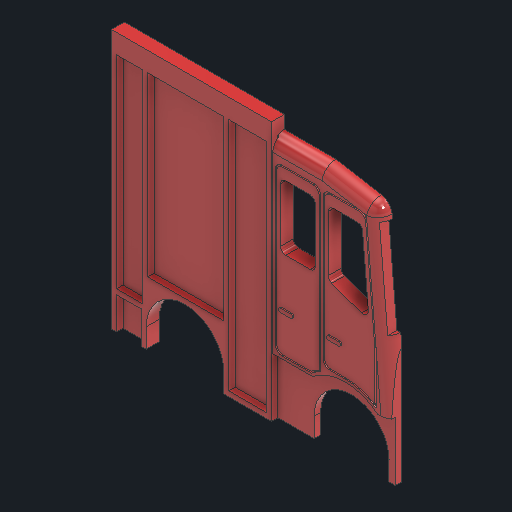
# Autodesk Inventor part: 7_1_1_cote_droit_base
Saved by Autodesk Inventor 2026 (Build 300175000, 175)
## iProperties
Created: 2025-06-21
Part Number: 7_1_1_cote_droit_base
Material: Generic
Document SubType Name: Modeling
Designer: remg9
Density: 1 g/cm^3
Appearance: Default
Author: remg9
Autodesk Inventor part; units mm, degrees
ref_plane "YZ Plane" through (0, 0, 0) normal (1, 0, 0) x (0, 1, 0)
ref_plane "XZ Plane" through (0, 0, 0) normal (0, 1, 0) x (-1, 0, 0)
ref_plane "XY Plane" through (0, 0, 0) normal (0, 0, 1) x (1, 0, 0)
sketch "Sketch1" plane through (0, 0, 0) normal (0, 0, 1) x (1, 0, 0)
  line L0 (0, 0) -> (215, 0) construction
  line L1 (215, 0) -> (215, 201) construction
  line L2 (215, 201) -> (0, 201) construction
  line L3 (0, 201) -> (0, 0)
  circle A0 centre (181, 15) radius 29 construction
  circle A1 centre (57, 15) radius 30 construction
  line L4 (0, 15) -> (215, 15) construction
  line L5 (124, 201) -> (124, 0) construction
  line L6 (0, 201) -> (124, 201)
  line L7 (124, 191) -> (215, 191) construction
  line L8 (164, 15) -> (164, 191) construction
  line L9 (124, 201) -> (124, 191)
  line L10 (124, 191) -> (164, 191)
  line L11 (215, 90) -> (0, 90) construction
  line L12 (215, 0) -> (215, 90)
  line L13 (215, 90) -> (191.4139, 359.5906) construction
  line L14 (164, 191) -> (320.5108, 163.4029) construction
  line L15 (210, 15) -> (210, 0) construction
  line L16 (152, 15) -> (152, 0) construction
  line L17 (87, 15) -> (87, 0) construction
  line L18 (27, 15) -> (27, 0) construction
  line L19 (0, 0) -> (27, 0)
  line L20 (27, 0) -> (27, 15)
  line L21 (87, 15) -> (87, 0)
  line L22 (152, 0) -> (152, 15)
  line L23 (87, 0) -> (152, 0)
  line L24 (210, 15) -> (210, 0)
  line L25 (210, 0) -> (215, 0)
  line L26 (164, 191) -> (199.2676, 184.7814)
  line L27 (215, 90) -> (207.493, 175.8049)
  arc A2 (87, 15) -> (27, 15) centre (57, 15) ccw
  arc A3 (210, 15) -> (152, 15) centre (181, 15) ccw
  arc A4 (207.493, 175.8049) -> (199.2676, 184.7814) centre (197.5311, 174.9333) ccw
  point P0 (84, 0)
  point P1 (24, 0)
  point P2 (206.8243, 183.4489)
  dimension "d0" = 201
  dimension "d1" = 215
  dimension "d2" = 58
  dimension "d3" = 60
  dimension "d4" = 34
  dimension "d5" = 57
  dimension "d6" = 15
  dimension "d7" = 15
  dimension "d8" = 91
  dimension "d9" = 10
  dimension "d10" = 40
  dimension "d11" = 90
  dimension "d12" = 10
  dimension "d13" = 5
  dimension "d14" = 10
  dimension "d44" = 5
  dimension "d99" = 124
  constraints: 54 end point, 17 point on line, 10 point on circle, 9 tangent, 6 collinear, 5 centre point, 5 vertical, 4 horizontal, 4 perpendicular, 2 coincident, 1 parallel, 10 other
  measures "d0" distance of L1.start L1.end
  measures "d1" distance of L1.end L2.end
  measures "d2" diameter of A0
  measures "d3" diameter of A1
  measures "d4" distance from line of L1 A0.centre
  measures "d5" distance from line of L3 A1.centre
  measures "d8" distance between parallel lines of L1 L5
  measures "d9" distance between parallel lines of L7 L2
  measures "d10" distance between parallel lines of L5 L8
  measures "d11" distance of the line from the sketch origin of L11
  measures "d12" angle of L14 L7
  measures "d13" angle of L13 L1
  measures "d14" radius of A4
  measures "d44" distance between parallel lines of L1 L15
  measures "d99" distance of A0.centre A1.centre
extrude "Extrusion1" add sketch "Sketch1" along normal blind 5
sketch "Sketch2" plane through (0, 0, 5) normal (0, 0, 1) x (1, 0, 0)
  line L0 (0, 0) -> (0, 201)
  line L1 (0, 201) -> (124, 201)
  line L2 (124, 201) -> (124, 0)
  line L3 (124, 0) -> (87, 0)
  line L4 (87, 0) -> (87, 15.2116)
  line L5 (27, 15.2116) -> (27, 0)
  line L6 (87, 0) -> (152, 0) projected
  line L7 (0, 201) -> (0, 0) projected
  line L8 (124, 201) -> (0, 201) projected
  line L9 (124, 191) -> (124, 201) projected
  line L10 (27, 0) -> (27, 15) projected
  line L11 (87, 15) -> (87, 0) projected
  line L12 (87, 15) -> (27, 15) construction
  arc A0 (87, 15) -> (27, 15) centre (57, 15) ccw
  line L13 (0, 0) -> (4, 0)
  line L14 (4, 0) -> (4, 25)
  line L15 (4, 25) -> (23, 25)
  line L16 (23, 25) -> (23, 0)
  line L17 (23, 0) -> (27, 0)
  line L18 (0, 0) -> (27, 0) projected
  line L19 (4, 186) -> (24, 186)
  line L20 (24, 186) -> (24, 29)
  line L21 (24, 29) -> (4, 29)
  line L22 (4, 29) -> (4, 186)
  line L23 (28, 186) -> (87, 186)
  line L24 (87, 186) -> (87, 49)
  line L25 (87, 49) -> (28, 49)
  line L26 (28, 49) -> (28, 186)
  line L27 (91, 186) -> (120, 186)
  line L28 (120, 186) -> (120, 4)
  line L29 (91, 4) -> (91, 186)
  line L30 (120, 4) -> (91, 4)
  point P0 (27, 7.5)
  point P1 (4, 107.5)
  point P2 (57, 45)
  point P3 (27, 15)
  dimension "d17" = 4
  dimension "d18" = 4
  dimension "d19" = 25
  dimension "d20" = 4
  dimension "d21" = 4
  dimension "d22" = 4
  dimension "d23" = 4
  dimension "d24" = 4
  dimension "d25" = 4
  dimension "d26" = 4
  dimension "d27" = 4
  dimension "d28" = 29
  dimension "d29" = 20
  dimension "d30" = 15
  constraints: 48 end point, 10 perpendicular, 6 collinear, 6 horizontal, 5 parallel, 3 point on circle, 3 point on line, 2 midpoint, 2 tangent, 1 centre point, 1 vertical
  measures "d17" distance between parallel lines of L0 L14
  measures "d18" distance from line of point (27, 7.5) L16
  measures "d19" distance between parallel lines of L18 L15
  measures "d20" distance from line of L0 point (4, 107.5)
  measures "d21" distance between parallel lines of L26 L20
  measures "d22" distance between parallel lines of L29 L24
  measures "d23" distance between parallel lines of L2 L28
  measures "d24" distance between parallel lines of L4 L29
  measures "d25" distance between parallel lines of L3 L30
  measures "d26" distance from line of L25 point (57, 45)
  measures "d27" distance between parallel lines of L15 L21
  measures "d28" distance between parallel lines of L28 L29
  measures "d29" distance between parallel lines of L22 L20
  measures "d30" distance between parallel lines of L1 L23
extrude "Extrusion2" add sketch "Sketch2" along normal blind 5 contours L0 L1 L2 L3 L4 A0 L5 L17 L16 L15 L14 L13
sketch "Sketch3" plane through (0, 0, 5) normal (0, 0, 1) x (1, 0, 0)
  line L0 (152, 15) -> (210, 15) construction
  line L1 (125, 45) -> (152, 45) construction
  line L2 (152, 45) -> (152, 0) construction
  line L3 (152, 0) -> (148.5552, 0)
  line L4 (148.5552, 0) -> (125, 0) construction
  line L5 (125, 0) -> (125, 45) construction
  line L6 (124, 0) -> (124, 201) construction
  arc A0 (215, 34.105) -> (152, 41.0768) centre (181, 15) ccw construction
  arc A1 (210, 15) -> (152, 15) centre (181, 15) ccw construction
  line L7 (215, 0) -> (215, 90) construction
  line L8 (124, 0) -> (152, 0) construction
  line L9 (152, 0) -> (152, 15) construction
  line L10 (125, 191) -> (125, 46)
  line L11 (125, 46) -> (155.7216, 46)
  line L12 (215, 46) -> (215, 90)
  line L13 (215, 90) -> (207.493, 175.8049)
  line L14 (199.2676, 184.7814) -> (164, 191)
  line L15 (164, 191) -> (125, 191)
  line L16 (164, 191) -> (124, 191) projected
  line L17 (199.2676, 184.7814) -> (164, 191) projected
  line L18 (215, 90) -> (207.493, 175.8049) projected
  arc A2 (206.2784, 46) -> (155.7216, 46) centre (181, 15) ccw
  arc A3 (207.493, 175.8049) -> (199.2676, 184.7814) centre (197.5311, 174.9333) ccw
  line L19 (215, 46) -> (206.2784, 46)
  point P0 (0, 0)
  dimension "d33" = 1
  dimension "d34" = 45
  dimension "d35" = 10
  dimension "d37" = 1
  dimension "d38" = 1
  dimension "d39" = 1
  dimension "d40" = 10
  constraints: 26 end point, 7 collinear, 6 point on circle, 3 centre point, 3 coincident, 3 horizontal, 3 perpendicular, 3 point on line, 2 tangent, 2 vertical, 1 midpoint
  measures "d33" distance between parallel lines of L6 L5
  measures "d34" distance between parallel lines of L4 L1
  measures "d35" radial gap between concentric circles of A1 A0
  measures "d37" distance between parallel lines of L6 L10
  measures "d38" distance between parallel lines of L1 L11
  measures "d39" radial gap between concentric circles of A2 A0
  measures "d40" radius of A3
extrude "Extrusion3" add sketch "Sketch3" along normal blind 5
sketch "Sketch4" plane through (0, 0, 10) normal (0, 0, 1) x (1, 0, 0)
  line L0 (207.7545, 172.8163) -> (214.1284, 99.9619)
  line L1 (214.1284, 99.9619) -> (211.1399, 99.7005)
  line L2 (211.1399, 99.7005) -> (204.7659, 172.5548)
  line L3 (204.7659, 172.5548) -> (207.7545, 172.8163)
  line L4 (215, 90) -> (207.493, 175.8049) projected
  point P0 (0, 0)
  dimension "d45" = 3
  dimension "d46" = 3
  dimension "d87" = 10
  dimension "d88" = 73.1326
  constraints: 8 end point, 3 perpendicular, 1 collinear
  measures "d45" distance between parallel lines of L0 L2
  measures "d46" distance from line of L3 L4.end
  measures "d87" distance from line of L4.start L1
  measures "d88" distance between parallel lines of L1 L3
extrude "Extrusion4" cut sketch "Sketch4" against normal through all
sketch "Sketch5" plane through (0, 0, 10) normal (0, 0, 1) x (1, 0, 0)
  line L0 (132, 48) -> (155.0192, 48)
  line L1 (162, 52.4566) -> (162, 171)
  line L2 (157, 176) -> (132, 176)
  line L3 (127, 171) -> (127, 53)
  line L4 (152, 15) -> (210, 15) construction
  arc A0 (162, 52.4566) -> (155.0192, 48) centre (181, 15) ccw
  line L5 (164, 171) -> (164, 62)
  line L6 (205, 49.4674) -> (205, 89.5634)
  line L7 (205, 89.5634) -> (197.8371, 171.4358)
  line L8 (192.8561, 176) -> (169, 176)
  line L9 (211.1399, 99.7005) -> (204.7659, 172.5548) projected
  line L10 (181, 57) -> (169, 57)
  arc A1 (205, 49.4674) -> (181, 57) centre (181, 15) ccw
  line L11 (125, 191) -> (125, 46) construction
  line L12 (125, 46) -> (155.7216, 46) construction
  arc A2 (206.2784, 46) -> (155.7216, 46) centre (181, 15) ccw construction
  line L13 (215, 46) -> (215, 90) construction
  line L14 (164, 191) -> (125, 191) construction
  line L15 (128, 170) -> (128, 54)
  line L16 (133, 49) -> (154.6751, 49)
  line L17 (181, 58) -> (170, 58)
  line L18 (165, 63) -> (165, 170)
  line L19 (170, 175) -> (191.9398, 175)
  line L20 (196.9208, 170.4358) -> (204, 89.5197)
  line L21 (204, 89.5197) -> (204, 51.3318)
  line L22 (133, 175) -> (156, 175)
  line L23 (161, 170) -> (161, 53.0657)
  arc A3 (161, 53.0657) -> (154.6751, 49) centre (181, 15) ccw
  arc A4 (204, 51.3318) -> (181, 58) centre (181, 15) ccw
  arc A5 (133, 175) -> (128, 170) centre (133, 170) ccw
  arc A6 (132, 176) -> (127, 171) centre (132, 171) ccw
  arc A7 (161, 170) -> (156, 175) centre (156, 170) ccw
  arc A8 (162, 171) -> (157, 176) centre (157, 171) ccw
  arc A9 (170, 175) -> (165, 170) centre (170, 170) ccw
  arc A10 (169, 176) -> (164, 171) centre (169, 171) ccw
  arc A11 (196.9208, 170.4358) -> (191.9398, 175) centre (191.9398, 170) ccw
  arc A12 (197.8371, 171.4358) -> (192.8561, 176) centre (192.8561, 171) ccw
  arc A13 (128, 54) -> (133, 49) centre (133, 54) ccw
  arc A14 (165, 63) -> (170, 58) centre (170, 63) ccw
  arc A15 (164, 62) -> (169, 57) centre (169, 62) ccw
  arc A16 (127, 53) -> (132, 48) centre (132, 53) ccw
  point P0 (0, 0)
  dimension "d49" = 2
  dimension "d50" = 2
  dimension "d53" = 2
  dimension "d54" = 2
  dimension "d55" = 2
  dimension "d56" = 7
  dimension "d57" = 10
  dimension "d58" = 15
  dimension "d59" = 35
  dimension "d60" = 1
  dimension "d62" = 1
  dimension "d63" = 1
  dimension "d64" = 1
  dimension "d65" = 1
  dimension "d66" = 1
  dimension "d67" = 1
  dimension "d68" = 1
  dimension "d69" = 1
  dimension "d70" = 1
  dimension "d71" = 5
  dimension "d72" = 5
  constraints: 38 end point, 32 point on circle, 25 tangent, 16 centre point, 11 equal radius, 6 parallel, 5 coincident, 5 horizontal, 5 perpendicular, 3 vertical, 1 collinear, 1 midpoint
  measures "d49" distance between parallel lines of L11 L3
  measures "d50" distance between parallel lines of L12 L0
  measures "d53" radial gap between concentric circles of A2 A1
  measures "d54" radial gap between concentric circles of A2 A0
  measures "d55" distance between parallel lines of L5 L1
  measures "d56" distance between parallel lines of L9 L7
  measures "d57" distance between parallel lines of L13 L6
  measures "d58" distance between parallel lines of L14 L2
  measures "d59" distance between parallel lines of L3 L1
  measures "d60" distance between parallel lines of L19 L8
  measures "d62" distance between parallel lines of L20 L7
  measures "d63" distance between parallel lines of L5 L18
  measures "d64" distance between parallel lines of L17 L10
  measures "d65" distance between parallel lines of L1 L23
  measures "d66" distance between parallel lines of L0 L16
  measures "d67" distance between parallel lines of L3 L15
  measures "d68" distance between parallel lines of L2 L22
  measures "d69" radial gap between concentric circles of A0 A3
  measures "d70" distance between parallel lines of L6 L21
  measures "d71" radius of A5
  measures "d72" radius of A16
extrude "Extrusion5" cut sketch "Sketch5" against normal blind 1
sketch "Sketch6" plane through (0, 0, 10) normal (0, 0, 1) x (1, 0, 0)
  line L0 (135, 167) -> (154, 167)
  line L1 (158, 163) -> (158, 121)
  line L2 (154, 117) -> (135, 117)
  line L3 (131, 121) -> (131, 163)
  line L4 (172, 167) -> (190.5446, 167)
  line L5 (194.5293, 163.3486) -> (199.043, 111.7569)
  line L6 (193.6902, 107.6495) -> (170.6319, 116.0421)
  line L7 (168, 119.8008) -> (168, 163)
  line L8 (128, 170) -> (128, 54) projected
  line L9 (161, 53.0657) -> (161, 170) projected
  line L10 (156, 175) -> (133, 175) projected
  line L11 (165, 170) -> (165, 63) projected
  line L12 (204, 89.5197) -> (196.9208, 170.4358) projected
  arc A0 (135, 167) -> (131, 163) centre (135, 163) ccw
  arc A1 (158, 163) -> (154, 167) centre (154, 163) ccw
  arc A2 (194.5293, 163.3486) -> (190.5446, 167) centre (190.5446, 163) ccw
  arc A3 (172, 167) -> (168, 163) centre (172, 163) ccw
  arc A4 (131, 121) -> (135, 117) centre (135, 121) ccw
  arc A5 (154, 117) -> (158, 121) centre (154, 121) ccw
  arc A6 (168, 119.8008) -> (170.6319, 116.0421) centre (172, 119.8008) ccw
  arc A7 (193.6902, 107.6495) -> (199.043, 111.7569) centre (195.0583, 111.4083) ccw
  point P0 (0, 0)
  point P1 (168, 167)
  point P2 (168, 117)
  dimension "d75" = 3
  dimension "d76" = 3
  dimension "d77" = 8
  dimension "d78" = 50
  dimension "d79" = 27
  dimension "d80" = 3
  dimension "d82" = 3
  dimension "d83" = 110
  dimension "d84" = 4
  constraints: 16 end point, 16 point on circle, 16 tangent, 8 centre point, 7 equal radius, 6 point on line, 3 parallel, 2 horizontal, 1 perpendicular
  measures "d75" distance between parallel lines of L8 L3
  measures "d76" distance between parallel lines of L9 L1
  measures "d77" distance between parallel lines of L10 L0
  measures "d78" distance between parallel lines of L0 L2
  measures "d79" distance between parallel lines of L1 L3
  measures "d80" distance between parallel lines of L11 L7
  measures "d82" distance between parallel lines of L12 L5
  measures "d83" angle of L7 L6
  measures "d84" radius of A0
extrude "Extrusion6" cut sketch "Sketch6" against normal through all
fillet "Fillet2" radius 10 6 edges at (144.5, 191, 10) (204.9039, 181.6892, 10) (207.6238, 174.3106, 10) (181.6338, 187.8907, 10) (215, 68, 10) (214.5642, 94.981, 10)
sketch "Sketch7" plane through (0, 0, 10) normal (0, 0, 1) x (1, 0, 0)
  line L0 (132, 79) -> (140, 79) construction
  line L1 (132, 77.5) -> (140, 77.5)
  line L2 (140, 80.5) -> (132, 80.5)
  arc A0 (132, 80.5) -> (132, 77.5) centre (132, 79) ccw
  arc A1 (140, 77.5) -> (140, 80.5) centre (140, 79) ccw
  line L3 (133, 49) -> (154.6751, 49) projected
  line L4 (128, 170) -> (128, 54) projected
  line L5 (169, 79) -> (177, 79) construction
  line L6 (169, 77.5) -> (177, 77.5)
  line L7 (177, 80.5) -> (169, 80.5)
  arc A2 (169, 80.5) -> (169, 77.5) centre (169, 79) ccw
  arc A3 (177, 77.5) -> (177, 80.5) centre (177, 79) ccw
  line L8 (165, 170) -> (165, 63) projected
  point P0 (0, 0)
  point P1 (136, 79)
  point P2 (173, 79)
  dimension "d90" = 8
  dimension "d91" = 3
  dimension "d92" = 30
  dimension "d93" = 8
  dimension "d94" = 8
  dimension "d95" = 3
  dimension "d96" = 8
  constraints: 16 end point, 8 point on circle, 8 tangent, 4 centre point, 2 horizontal, 2 midpoint, 2 parallel, 1 collinear
  measures "d90" distance of L0.start L0.end
  measures "d91" distance between parallel lines of L1 L2
  measures "d92" distance from line of L3 point (136, 79)
  measures "d93" distance from line of L4 point (136, 79)
  measures "d94" distance of L5.start L5.end
  measures "d95" distance between parallel lines of L6 L7
  measures "d96" distance from line of L8 point (173, 79)
extrude "Extrusion7" add sketch "Sketch7" along normal blind 1
sketch "Sketch8" plane through (0, 0, 0) normal (0, 0, -1) x (-1, 0, 0)
  line L0 (-154.5, 188.5) -> (-123.5, 188.5)
  line L1 (-123.5, 188.5) -> (-123.5, 185.5)
  line L2 (-123.5, 185.5) -> (-154.5, 185.5)
  line L3 (-154.5, 185.5) -> (-154.5, 188.5)
  line L4 (-164, 191) -> (-124, 191) projected
  line L5 (-124, 191) -> (-124, 201) projected
  line L6 (-10.5, 186.5) -> (-7.5, 186.5)
  line L7 (-7.5, 186.5) -> (-7.5, 155.5)
  line L8 (-7.5, 155.5) -> (-10.5, 155.5)
  line L9 (-10.5, 155.5) -> (-10.5, 186.5)
  line L10 (-10.5, 40.5) -> (-7.5, 40.5)
  line L11 (-7.5, 40.5) -> (-7.5, 9.5)
  line L12 (-7.5, 9.5) -> (-10.5, 9.5)
  line L13 (-10.5, 9.5) -> (-10.5, 40.5)
  line L14 (0, 201) -> (0, 0) projected
  line L15 (-124, 201) -> (0, 201) projected
  line L16 (0, 0) -> (-27, 0) projected
  point P0 (-123.5, 187)
  point P1 (-139, 188.5)
  point P2 (-9, 186.5)
  point P3 (-7.5, 171)
  point P4 (-7.5, 25)
  dimension "d100" = 3
  dimension "d101" = 31
  dimension "d106" = 4
  dimension "d107" = 15
  dimension "d108" = 31
  dimension "d109" = 3
  dimension "d110" = 9
  dimension "d111" = 30
  dimension "d112" = 25
  constraints: 24 end point, 6 parallel, 5 midpoint, 3 horizontal, 3 perpendicular, 2 point on line, 1 collinear
  measures "d100" distance of L0.end L1.end
  measures "d101" distance of L1.end L2.end
  measures "d106" distance from line of L4 point (-123.5, 187)
  measures "d107" distance from line of L5 point (-139, 188.5)
  measures "d108" distance of L8.end L6.start
  measures "d109" distance of L6.start L6.end
  measures "d110" distance from line of L14 point (-9, 186.5)
  measures "d111" distance from line of L15 point (-7.5, 171)
  measures "d112" distance from line of L16 point (-7.5, 25)
extrude "Extrusion8" cut sketch "Sketch8" against normal blind 3
sketch "Sketch9" plane through (0, 0, 0) normal (0, 0, -1) x (-1, 0, 0)
  line L0 (-194.7659, 176) -> (-126, 176)
  line L1 (-131, 171) -> (-194.7659, 171)
  line L2 (-194.7659, 171) -> (-194.7659, 176)
  line L3 (-121, 161) -> (-121, 102.4083)
  line L4 (-116, 97.4083) -> (-116, 161)
  line L5 (-205, 92.4083) -> (-131, 92.4083)
  line L6 (-126, 87.4083) -> (-190, 87.4083)
  line L7 (-205, 87.4083) -> (-205, 92.4083)
  line L8 (-164, 191) -> (-124, 191) projected
  line L9 (-215, 0) -> (-215, 90) projected
  line L10 (-204.7659, 172.5548) -> (-211.1399, 99.7005) projected
  line L11 (-131, 163) -> (-131, 121) projected
  arc A0 (-199.043, 111.7569) -> (-193.6902, 107.6495) centre (-195.0583, 111.4083) ccw projected
  arc A1 (-121, 161) -> (-131, 171) centre (-131, 161) ccw
  arc A2 (-131, 92.4083) -> (-121, 102.4083) centre (-131, 102.4083) ccw
  arc A3 (-126, 87.4083) -> (-116, 97.4083) centre (-126, 97.4083) ccw
  line L12 (-205, 92.4083) -> (-200, 92.4083)
  line L13 (-200, 77.4083) -> (-200, 52.4083)
  line L14 (-200, 52.4083) -> (-205, 52.4083)
  line L15 (-205, 52.4083) -> (-205, 92.4083)
  arc A4 (-190, 87.4083) -> (-200, 77.4083) centre (-190, 77.4083) ccw
  line L16 (-137.5506, 176) -> (-15, 176)
  line L17 (-15, 176) -> (-15, 171)
  line L18 (-15, 171) -> (-106, 171)
  arc A5 (-106, 171) -> (-116, 161) centre (-106, 161) ccw
  line L19 (0, 201) -> (0, 0) projected
  point P0 (-116, 166)
  point P1 (-194.7659, 173.5)
  point P2 (-200, 64.9083)
  dimension "d115" = 15
  dimension "d116" = 5
  dimension "d117" = 5
  dimension "d118" = 5
  dimension "d119" = 10
  dimension "d121" = 10
  dimension "d122" = 10
  dimension "d123" = 15
  dimension "d124" = 10
  dimension "d127" = 5
  dimension "d128" = 10
  dimension "d129" = 40
  dimension "d130" = 10
  dimension "d131" = 5
  dimension "d132" = 15
  constraints: 30 end point, 10 point on circle, 10 tangent, 6 parallel, 5 centre point, 5 point on line, 4 horizontal, 2 equal radius, 2 midpoint, 2 perpendicular
  measures "d115" distance between parallel lines of L8 L0
  measures "d116" distance of L1.end L0.start
  measures "d117" distance between parallel lines of L4 L3
  measures "d118" distance between parallel lines of L6 L5
  measures "d119" distance between parallel lines of L9 L7
  measures "d121" horizontal distance of point (-194.766, 173.5) L10.start
  measures "d122" distance between parallel lines of L11 L3
  measures "d123" distance edge to line of A0 L5
  measures "d124" radius of A1
  measures "d127" distance from line of L15 point (-200, 64.908)
  measures "d128" radius of A4
  measures "d129" distance of L14.end L5.start
  measures "d130" radius of A5
  measures "d131" distance between parallel lines of L16 L18
  measures "d132" distance between parallel lines of L19 L17
extrude "Extrusion9" cut sketch "Sketch9" against normal blind 3
body "Solid1"
